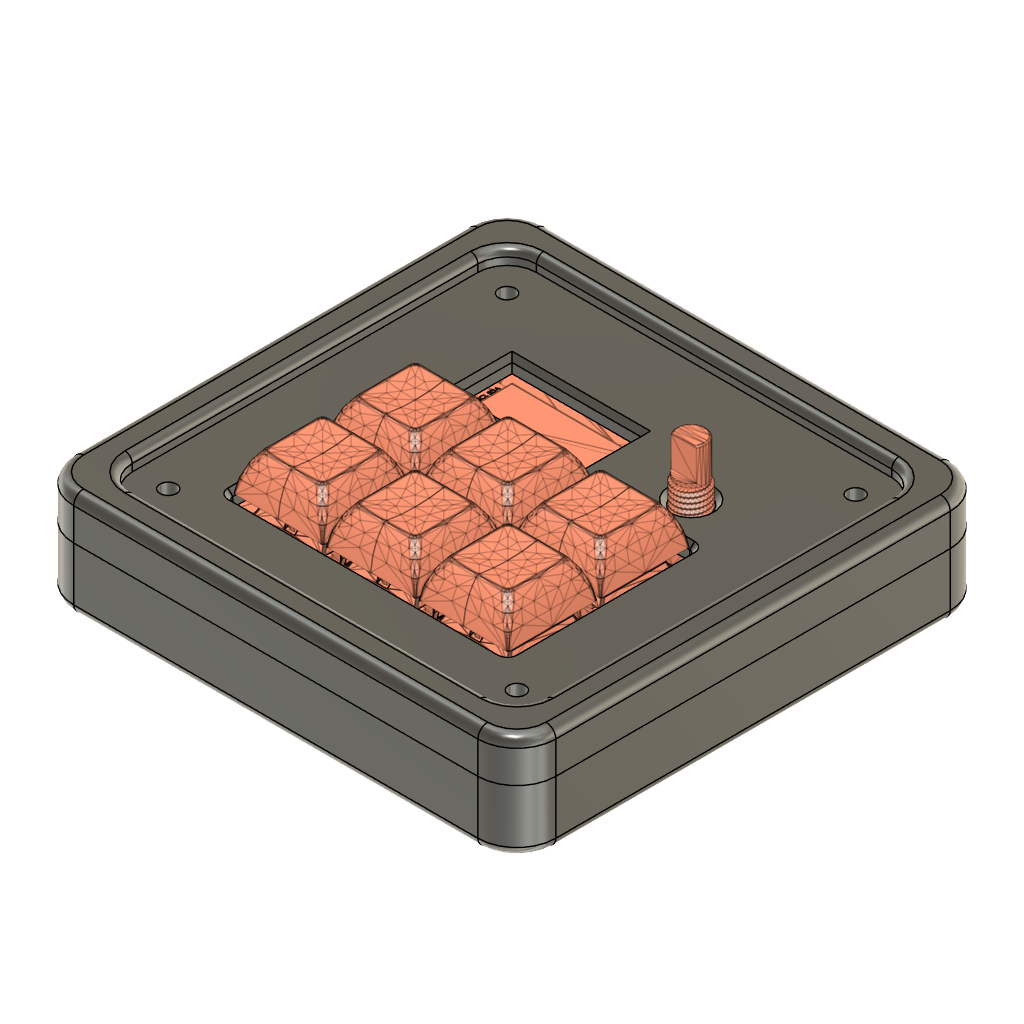
SpacePad-asssembled (Autodesk Fusion 360 archive; units mm, degrees)
design "SpacePad-Case.f3d"
part number: 2026-09-18-11-28-58-965
Autodesk Fusion 360 part; units mm, degrees
(part 1 of 3)
other "Base Mesh Feature4"
other "MeshRepair5"
sketch "Sketch97" plane through (0, 0, 0) normal (0, 0, 1) x (1, 0, 0)
  line L0 (39.25, 38.25) -> (-39.25, -38.25) construction
  line L1 (-39.25, 38.25) -> (39.25, -38.25) construction
  line L2 (-35.25, -38.45) -> (35.25, -38.45)
  arc A0 (35.25, -38.45) -> (39.45, -34.25) centre (35.25, -34.25) ccw
  line L3 (39.45, -34.25) -> (39.45, 34.25)
  arc A1 (39.45, 34.25) -> (35.25, 38.45) centre (35.25, 34.25) ccw
  line L4 (35.25, 38.45) -> (-35.25, 38.45)
  arc A2 (-35.25, 38.45) -> (-39.45, 34.25) centre (-35.25, 34.25) ccw
  line L5 (-39.45, 34.25) -> (-39.45, -34.25)
  arc A3 (-39.45, -34.25) -> (-35.25, -38.45) centre (-35.25, -34.25) ccw
  dimension "d507" = 78.5
  dimension "d508" = 76.5
  constraint coincident L0 origin
  constraint coincident L1 origin
  measures "d507" distance of L0.end L1.end
  measures "d508" distance of L1.start L0.end
extrude "Extrude107" add sketch "Sketch97" against normal blind 3 makes body 1
sketch "Sketch98" plane through (0, 0, -3) normal (0, 0, -1) x (1, 0, 0)
  arc A0 (-35.25, 38.45) -> (-39.45, 34.25) centre (-35.25, 34.25) ccw
  line L0 (-39.45, 34.25) -> (-39.45, -34.25)
  arc A1 (-39.45, -34.25) -> (-35.25, -38.45) centre (-35.25, -34.25) ccw
  line L1 (-35.25, -38.45) -> (35.25, -38.45)
  arc A2 (35.25, -38.45) -> (39.45, -34.25) centre (35.25, -34.25) ccw
  line L2 (39.45, -34.25) -> (39.45, 34.25)
  arc A3 (39.45, 34.25) -> (35.25, 38.45) centre (35.25, 34.25) ccw
  line L3 (35.25, 38.45) -> (-35.25, 38.45)
  line L4 (49.45, -40.45) -> (49.45, 40.45)
  line L5 (41.45, 48.45) -> (-41.45, 48.45)
  line L6 (-49.45, 40.45) -> (-49.45, -40.45)
  line L7 (-41.45, -48.45) -> (41.45, -48.45)
  arc A4 (-49.45, -40.45) -> (-41.45, -48.45) centre (-41.45, -40.45) ccw
  arc A5 (41.45, -48.45) -> (49.45, -40.45) centre (41.45, -40.45) ccw
  arc A6 (49.45, 40.45) -> (41.45, 48.45) centre (41.45, 40.45) ccw
  arc A7 (-41.45, 48.45) -> (-49.45, 40.45) centre (-41.45, 40.45) ccw
  dimension "d514" = 10
  dimension "d515" = 10
  dimension "d516" = 10
  dimension "d517" = 10
  dimension "d518" = 8
  constraint tangent L7 A4
  constraint tangent L6 A4
  constraint tangent L7 A5
  constraint tangent L4 A5
  constraint equal A4 A5
  constraint tangent L4 A6
  constraint tangent L5 A6
  constraint equal A4 A6
  constraint tangent L5 A7
  constraint tangent L6 A7
  constraint equal A4 A7
  measures "d514" distance of L2 L4
  measures "d515" distance of L3 L5
  measures "d516" distance of L0 L6
  measures "d517" distance of L1 L7
  measures "d518" radius of A4
extrude "Extrude108" add sketch "Sketch98" against normal blind 13 bodies 1
sketch "Sketch99" plane through (0, 0, 0) normal (0, 0, 1) x (-1, 0, 0)
  arc A0 (39.45, 34.25) -> (35.25, 38.45) centre (35.25, 34.25) ccw
  line L0 (35.25, 38.45) -> (-35.25, 38.45)
  arc A1 (-35.25, 38.45) -> (-39.45, 34.25) centre (-35.25, 34.25) ccw
  line L1 (-39.45, 34.25) -> (-39.45, -34.25)
  arc A2 (-39.45, -34.25) -> (-35.25, -38.45) centre (-35.25, -34.25) ccw
  line L2 (-35.25, -38.45) -> (35.25, -38.45)
  arc A3 (35.25, -38.45) -> (39.45, -34.25) centre (35.25, -34.25) ccw
  line L3 (39.45, -34.25) -> (39.45, 34.25)
  circle A4 centre (-35.7393, 34.7536) radius 2.35
  circle A5 centre (35.6945, 34.7057) radius 2.35
  circle A6 centre (-35.7505, -34.7482) radius 2.35
  circle A7 centre (35.7575, -34.7463) radius 2.35
  circle A8 centre (35.7575, -34.7463) radius 3.5
  circle A9 centre (-35.7505, -34.7482) radius 3.5
  circle A10 centre (-35.7393, 34.7536) radius 3.5
  circle A11 centre (35.6945, 34.7057) radius 3.5
  line L4 (35.6945, 31.2057) -> (39.45, 31.2057)
  line L5 (32.1945, 34.7057) -> (32.1945, 38.45)
  line L6 (32.2575, -34.7463) -> (32.2575, -38.45)
  line L7 (35.7575, -31.2463) -> (39.45, -31.2463)
  line L8 (-32.2505, -34.7482) -> (-32.2505, -38.45)
  line L9 (-35.7505, -31.2482) -> (-39.45, -31.2482)
  line L10 (-35.7393, 31.2536) -> (-39.45, 31.2536)
  line L11 (-32.2393, 34.7536) -> (-32.2393, 38.45)
  dimension "d521" = 4.7
  dimension "d522" = 4.7
  dimension "d523" = 4.7
  dimension "d524" = 4.7
  dimension "d525" = 7
  dimension "d526" = 7
  dimension "d527" = 7
  dimension "d528" = 7
  constraint concentric A7 A8
  constraint concentric A6 A9
  constraint concentric A4 A10
  constraint concentric A5 A11
  constraint coincident A11 L4.start
  constraint coincident L3 L4.end
  constraint tangent A11 L4
  constraint perpendicular L3 L4
  constraint coincident A11 L5.start
  constraint coincident L0 L5.end
  constraint tangent A11 L5
  constraint perpendicular L0 L5
  constraint coincident A8 L6.start
  constraint coincident L2 L6.end
  constraint tangent A8 L6
  constraint perpendicular L2 L6
  constraint coincident A8 L7.start
  constraint coincident L3 L7.end
  constraint tangent A8 L7
  constraint perpendicular L3 L7
  constraint coincident A9 L8.start
  constraint coincident L2 L8.end
  constraint tangent A9 L8
  constraint perpendicular L2 L8
  constraint coincident A9 L9.start
  constraint coincident L1 L9.end
  constraint tangent A9 L9
  constraint perpendicular L1 L9
  constraint coincident A10 L10.start
  constraint coincident L1 L10.end
  constraint tangent A10 L10
  constraint perpendicular L1 L10
  constraint coincident A10 L11.start
  constraint coincident L0 L11.end
  constraint tangent A10 L11
  constraint perpendicular L0 L11
  measures "d521" diameter of A4
  measures "d522" diameter of A5
  measures "d523" diameter of A6
  measures "d524" diameter of A7
  measures "d525" diameter of A8
  measures "d526" diameter of A9
  measures "d527" diameter of A10
  measures "d528" diameter of A11
extrude "Extrude109" add sketch "Sketch99" along normal blind 4 contours A0 L0 L3 A11 L4 L5 | A3 L3 A8 L7 | A11 | L0 A1 A10 L11 | A3 A8 | A1 A10 | L2 A3 A8 L6 | A1 L1 A10 L10 | A2 L2 A9 L8 | L1 A2 A9 L9 | A2 A9 picked at (38.4851, -36.238) picked at (-35.9802, -31.6463) bodies 1
other "Modify12"
other "Modify13"
sketch "Sketch100" plane through (0, 48.45, 0) normal (0, 1, 0) x (-1, 0, 0)
  line L0 (41.45, -3) -> (41.45, 10)
  line L1 (41.45, 10) -> (-41.45, 10)
  line L2 (-41.45, 10) -> (-41.45, -3)
  line L3 (-4.6681, 1.5118) -> (-4.6681, 1.1341)
  line L4 (-4.6681, 1.1341) -> (-4.6681, 0.8012)
  arc A0 (-4.6681, 0.8012) -> (-3.2181, -0.6488) centre (-3.2181, 0.8012) ccw
  line L5 (-3.2181, -0.6488) -> (3.2225, -0.6488)
  arc A1 (3.2225, -0.6488) -> (4.6725, 0.8012) centre (3.2225, 0.8012) ccw
  line L6 (4.6725, 0.8012) -> (4.6725, 1.1341)
  line L7 (4.6725, 1.1341) -> (4.6725, 1.5118)
  arc A2 (4.6725, 1.5118) -> (3.2225, 2.9618) centre (3.2225, 1.5118) ccw
  line L8 (3.2225, 2.9618) -> (-3.2181, 2.9618)
  arc A3 (-3.2181, 2.9618) -> (-4.6681, 1.5118) centre (-3.2181, 1.5118) ccw
  line L9 (-41.45, -3) -> (41.45, -3)
extrude "Extrude110" cut sketch "Sketch100" against normal blind 10 contours L3 L4 A0 L5 A1 L6 L7 A2 L8 A3 bodies 1
extrude "Extrude111" cut 1 faces at (-1.0756, 38.45, -0.2163) along direction (0, -1, 0) blind 1 on bodies 1 bodies 1
extrude "Extrude112" cut 1 faces at (-1.0756, 37.45, -0.2163) along direction (0, -1, 0) blind 0.001 on bodies 1 bodies 1
extrude "Extrude113" cut 1 faces at (-1.0756, 37.449, -0.2163) along direction (0, -1, 0) blind 8.5 on bodies 1 bodies 1
fillet "Fillet30" radius 2 8 edges at (-49.45, 0, -3) (-47.1069, 46.1069, -3) (0, 48.45, -3) (47.1069, 46.1069, -3) (49.45, 0, -3) (47.1069, -46.1069, -3) (0, -48.45, -3) (-47.1069, -46.1069, -3) on bodies 1
extrude "Extrude114" cut 1 faces at (-1.0756, 28.949, -0.2163) along direction (0, -1, 0) blind 3 on bodies 1 bodies 1
extrude "Extrude115" cut 1 faces at (-1.0756, 25.949, -0.2163) along direction (0, -1, 0) blind 0.5 on bodies 1 bodies 1
sketch "Sketch101" plane through (0, 0, 0) normal (0, 0, 1) x (1, 0, 0)
  line L0 (39.25, 38.25) -> (-39.25, -38.25) construction
  line L1 (-39.25, 38.25) -> (39.25, -38.25) construction
  line L2 (-35.45, -38.45) -> (35.45, -38.45)
  line L3 (39.45, -34.45) -> (39.45, 34.45)
  line L4 (35.45, 38.45) -> (-35.45, 38.45)
  line L5 (-39.45, 34.45) -> (-39.45, -34.45)
  arc A0 (-35.45, 38.45) -> (-39.45, 34.45) centre (-35.45, 34.45) ccw
  arc A1 (39.45, 34.45) -> (35.45, 38.45) centre (35.45, 34.45) ccw
  arc A2 (35.45, -38.45) -> (39.45, -34.45) centre (35.45, -34.45) ccw
  arc A3 (-39.45, -34.45) -> (-35.45, -38.45) centre (-35.45, -34.45) ccw
  line L6 (27.56, -29.5) -> (-27.77, -29.5)
  line L7 (-28.77, -28.5) -> (-28.77, 7.9)
  line L8 (-27.77, 8.9) -> (27.56, 8.9)
  line L9 (28.56, 7.9) -> (28.56, -28.5)
  arc A4 (27.56, -29.5) -> (28.56, -28.5) centre (27.56, -28.5) ccw
  arc A5 (-28.77, -28.5) -> (-27.77, -29.5) centre (-27.77, -28.5) ccw
  arc A6 (-27.77, 8.9) -> (-28.77, 7.9) centre (-27.77, 7.9) ccw
  arc A7 (28.56, 7.9) -> (27.56, 8.9) centre (27.56, 7.9) ccw
  line L10 (2.4481, 12.55) -> (-23.9519, 12.55)
  line L11 (-23.9519, 12.55) -> (-23.9519, 23.95)
  line L12 (-23.9519, 23.95) -> (2.4481, 23.95)
  line L13 (2.4481, 23.95) -> (2.4481, 12.55)
  circle A8 centre (19.7639, 16.9931) radius 3.6
  dimension "d549" = 78.5
  dimension "d550" = 76.5
  dimension "d552" = 4
  dimension "d556" = 1
  dimension "d558" = 7.2
  constraint coincident L0 origin
  constraint coincident L1 origin
  constraint tangent L4 A0
  constraint tangent L5 A0
  constraint tangent L4 A1
  constraint tangent L3 A1
  constraint equal A0 A1
  constraint tangent L3 A2
  constraint tangent L2 A2
  constraint equal A0 A2
  constraint tangent L2 A3
  constraint tangent L5 A3
  constraint equal A0 A3
  constraint tangent L9 A4
  constraint tangent L6 A4
  constraint tangent L6 A5
  constraint tangent L7 A5
  constraint equal A4 A5
  constraint tangent L7 A6
  constraint tangent L8 A6
  constraint equal A4 A6
  constraint tangent L8 A7
  constraint tangent L9 A7
  constraint equal A4 A7
  measures "d549" distance of L0.end L1.end
  measures "d550" distance of L1.start L0.end
  measures "d552" radius of A0
  measures "d556" radius of A4
  measures "d558" diameter of A8
extrude "Extrude116" add sketch "Sketch101" along normal blind 3 separate body makes body 2
chamfer "Chamfer18" distance 1 angle 45 8 edges at (-0.105, 8.9, 3) (28.2671, 8.6071, 3) (28.56, -10.3, 3) (28.2671, -29.2071, 3) (-0.105, -29.5, 3) (-28.4771, -29.2071, 3) (-28.77, -10.3, 3) (-28.4771, 8.6071, 3) tangent chain off on bodies 2
chamfer "Chamfer19" distance 1 angle 45 4 edges at (-10.7519, 23.95, 3) (2.4481, 18.25, 3) (-10.7519, 12.55, 3) (-23.9519, 18.25, 3) tangent chain off on bodies 2
chamfer "Chamfer20" distance 1 angle 45 1 edges at (16.4076, 18.2949, 3) tangent chain off on bodies 2
sketch "Sketch102" plane through (0, 0, 3) normal (0, 0, 1) x (-1, 0, 0)
  line L0 (-3.4481, -11.55) -> (24.9519, -11.55)
  line L1 (24.9519, -11.55) -> (24.9519, -24.95)
  line L2 (24.9519, -24.95) -> (-3.4481, -24.95)
  line L3 (-3.4481, -24.95) -> (-3.4481, -11.55)
  arc A0 (39.45, 34.45) -> (35.45, 38.45) centre (35.45, 34.45) ccw
  line L4 (35.45, 38.45) -> (-35.45, 38.45)
  arc A1 (-35.45, 38.45) -> (-39.45, 34.45) centre (-35.45, 34.45) ccw
  line L5 (-39.45, 34.45) -> (-39.45, -34.45)
  arc A2 (-39.45, -34.45) -> (-35.45, -38.45) centre (-35.45, -34.45) ccw
  line L6 (-35.45, -38.45) -> (35.45, -38.45)
  arc A3 (35.45, -38.45) -> (39.45, -34.45) centre (35.45, -34.45) ccw
  line L7 (39.45, -34.45) -> (39.45, 34.45)
  line L8 (27.77, -9.9) -> (-27.56, -9.9)
  arc A4 (-29.56, -7.9) -> (-27.56, -9.9) centre (-27.56, -7.9) ccw
  line L9 (-29.56, -7.9) -> (-29.56, 28.5)
  arc A5 (-27.56, 30.5) -> (-29.56, 28.5) centre (-27.56, 28.5) ccw
  line L10 (-27.56, 30.5) -> (27.77, 30.5)
  arc A6 (29.77, 28.5) -> (27.77, 30.5) centre (27.77, 28.5) ccw
  line L11 (29.77, 28.5) -> (29.77, -7.9)
  arc A7 (27.77, -9.9) -> (29.77, -7.9) centre (27.77, -7.9) ccw
  circle A8 centre (-19.7639, -16.9931) radius 4.6
  line L12 (41.45, 48.45) -> (-41.45, 48.45)
  line L13 (-49.45, 40.45) -> (-49.45, -40.45)
  line L14 (-41.45, -48.45) -> (41.45, -48.45)
  line L15 (49.45, -40.45) -> (49.45, 40.45)
  arc A9 (41.45, -48.45) -> (49.45, -40.45) centre (41.45, -40.45) ccw
  arc A10 (-49.45, -40.45) -> (-41.45, -48.45) centre (-41.45, -40.45) ccw
  arc A11 (-41.45, 48.45) -> (-49.45, 40.45) centre (-41.45, 40.45) ccw
  arc A12 (49.45, 40.45) -> (41.45, 48.45) centre (41.45, 40.45) ccw
  dimension "d565" = 10
  dimension "d566" = 10
  dimension "d567" = 10
  dimension "d568" = 10
  dimension "d569" = 8
  constraint tangent L14 A9
  constraint tangent L15 A9
  constraint tangent L14 A10
  constraint tangent L13 A10
  constraint equal A9 A10
  constraint tangent L13 A11
  constraint tangent L12 A11
  constraint equal A9 A11
  constraint tangent L12 A12
  constraint tangent L15 A12
  constraint equal A9 A12
  measures "d565" distance of L4 L12
  measures "d566" distance of L5 L13
  measures "d567" distance of L6 L14
  measures "d568" distance of L7 L15
  measures "d569" radius of A9
extrude "Extrude117" add sketch "Sketch102" against normal blind 10 contours L12 L13 L14 L15 A9 A10 A11 A12 bodies 2
move_body "Move9" bodies 2 to x (1, 0, 0) y (0, 1, 0) z (0, 0, 1) at (0, 0, 5)
move_body "Move10" bodies 2 to x (1, 0, 0) y (0, 1, 0) z (0, 0, 1) at (0, 0, 7.63)
extrude "Extrude118" cut 1 faces at (11.8167, -45.1167, 5.63) along direction (0, 0, 1) blind 4.37 on bodies 2 bodies 2
delete_face "DeleteFace30" 8 faces at (-45.4319, -47.3469, -1.3785) (13.8167, -46.5452, -2.9977) (-47.5452, -13.4833, -2.9977) (46.0695, -46.9372, -1.3785) (47.5452, 13.4833, -2.9977) (46.3729, 46.71, -1.3785) (-13.8167, 46.5452, -2.9977) (-48.3469, 44.4319, -1.3785) on bodies 1
fillet "Fillet31" radius 2 16 edges at (0, -48.45, -3) (-47.1069, -46.1069, -3) (-49.45, 0, -3) (-47.1069, 46.1069, -3) (0, 48.45, -3) (47.1069, 46.1069, -3) (49.45, 0, -3) (47.1069, -46.1069, -3) (0, 48.45, 15.63) (-47.1069, 46.1069, 15.63) (-49.45, 0, 15.63) (-47.1069, -46.1069, 15.63) (0, -48.45, 15.63) (47.1069, -46.1069, 15.63) (49.45, 0, 15.63) (47.1069, 46.1069, 15.63) on bodies 1 2
sketch "Sketch103" plane through (0, 0, 12.63) normal (0, 0, -1) x (1, 0, 0)
  arc A0 (28.56, 28.5) -> (27.56, 29.5) centre (27.56, 28.5) ccw
  line L0 (28.56, 28.5) -> (28.56, -7.9)
  arc A1 (27.56, -8.9) -> (28.56, -7.9) centre (27.56, -7.9) ccw
  line L1 (27.56, -8.9) -> (-27.77, -8.9)
  arc A2 (-28.77, -7.9) -> (-27.77, -8.9) centre (-27.77, -7.9) ccw
  line L2 (-28.77, -7.9) -> (-28.77, 28.5)
  arc A3 (-27.77, 29.5) -> (-28.77, 28.5) centre (-27.77, 28.5) ccw
  line L3 (-27.77, 29.5) -> (27.56, 29.5)
  circle A4 centre (19.7639, -16.9931) radius 3.6
  line L4 (2.4481, -23.95) -> (-23.9519, -23.95)
  line L5 (-23.9519, -23.95) -> (-23.9519, -12.55)
  line L6 (-23.9519, -12.55) -> (2.4481, -12.55)
  line L7 (2.4481, -12.55) -> (2.4481, -23.95)
  arc A5 (-35.45, 38.45) -> (-39.45, 34.45) centre (-35.45, 34.45) ccw
  line L8 (-39.45, 34.45) -> (-39.45, -34.45)
  arc A6 (-39.45, -34.45) -> (-35.45, -38.45) centre (-35.45, -34.45) ccw
  line L9 (-35.45, -38.45) -> (35.45, -38.45)
  arc A7 (35.45, -38.45) -> (39.45, -34.45) centre (35.45, -34.45) ccw
  line L10 (39.45, -34.45) -> (39.45, 34.45)
  arc A8 (39.45, 34.45) -> (35.45, 38.45) centre (35.45, 34.45) ccw
  line L11 (35.45, 38.45) -> (-35.45, 38.45)
  circle A9 centre (35.7497, 34.7499) radius 1.7
  circle A10 centre (-35.7575, 34.7473) radius 1.7
  circle A11 centre (35.7482, -34.7503) radius 1.7
  circle A12 centre (-35.7567, -34.7538) radius 1.7
  dimension "d576" = 3.4
  dimension "d577" = 3.4
  dimension "d578" = 3.4
  dimension "d579" = 3.4
  measures "d576" diameter of A9
  measures "d577" diameter of A10
  measures "d578" diameter of A11
  measures "d579" diameter of A12
extrude "Extrude119" cut sketch "Sketch103" against normal blind 3 contours A9 | A10 | A11 | A12 bodies 2
sketch "Sketch104" plane through (0, 0, -3) normal (0, 0, -1) x (1, 0, 0)
  line L0 (41.45, 46.45) -> (-41.45, 46.45)
  arc A0 (-41.45, 46.45) -> (-47.45, 40.45) centre (-41.45, 40.45) ccw
  line L1 (-47.45, 40.45) -> (-47.45, -40.45)
  arc A1 (-47.45, -40.45) -> (-41.45, -46.45) centre (-41.45, -40.45) ccw
  line L2 (-41.45, -46.45) -> (41.45, -46.45)
  arc A2 (41.45, -46.45) -> (47.45, -40.45) centre (41.45, -40.45) ccw
  line L3 (47.45, -40.45) -> (47.45, 40.45)
  arc A3 (47.45, 40.45) -> (41.45, 46.45) centre (41.45, 40.45) ccw
  spline S0 degree 3 poles (4.3219, 28.9081) (4.3299, 29.059) (4.306, 29.3606) (4.2822, 29.5035) knots 0 0 0 0 1 1 1 1
  spline S1 degree 3 poles (4.2822, 29.5035) (4.2584, 29.6463) (4.2267, 29.6622) (4.1632, 29.7416) knots 0 0 0 0 1 1 1 1
  spline S2 degree 3 poles (4.1632, 29.7416) (4.0997, 29.821) (4.06, 29.9083) (3.925, 29.9797) knots 0 0 0 0 1 1 1 1
  spline S3 degree 3 poles (3.925, 29.9797) (3.7901, 30.0511) (3.5361, 30.1543) (3.3694, 30.1781) knots 0 0 0 0 1 1 1 1
  spline S4 degree 3 poles (3.3694, 30.1781) (3.2027, 30.202) (3.0678, 30.1702) (2.9329, 30.1385) knots 0 0 0 0 1 1 1 1
  spline S5 degree 3 poles (2.9329, 30.1385) (2.7979, 30.1067) (2.7503, 30.1385) (2.5757, 29.9797) knots 0 0 0 0 1 1 1 1
  spline S6 degree 3 poles (2.5757, 29.9797) (2.401, 29.821) (2.2502, 29.7178) (1.8613, 29.186) knots 0 0 0 0 1 1 1 1
  spline S7 degree 3 poles (1.8613, 29.186) (1.4724, 28.6542) (0.5516, 27.2333) (0.2341, 26.8047) knots 0 0 0 0 1 1 1 1
  spline S8 degree 3 poles (0.2341, 26.8047) (-0.0834, 26.3761) (0.0754, 26.5666) (-0.0437, 26.6063) knots 0 0 0 0 1 1 1 1
  spline S9 degree 3 poles (-0.0437, 26.6063) (-0.1628, 26.646) (-0.139, 26.5745) (-0.4803, 27.0428) knots 0 0 0 0 1 1 1 1
  spline S10 degree 3 poles (-0.4803, 27.0428) (-0.8216, 27.5111) (-1.7344, 28.932) (-2.1075, 29.4241) knots 0 0 0 0 1 1 1 1
  spline S11 degree 3 poles (-2.1075, 29.4241) (-2.4805, 29.9162) (-2.5281, 29.8924) (-2.7028, 30.0194) knots 0 0 0 0 1 1 1 1
  spline S12 degree 3 poles (-2.7028, 30.0194) (-2.8774, 30.1464) (-2.9965, 30.1543) (-3.1393, 30.1781) knots 0 0 0 0 1 1 1 1
  spline S13 degree 3 poles (-3.1393, 30.1781) (-3.2822, 30.202) (-3.4568, 30.194) (-3.5759, 30.1781) knots 0 0 0 0 1 1 1 1
  spline S14 degree 3 poles (-3.5759, 30.1781) (-3.695, 30.1623) (-3.7346, 30.1702) (-3.8537, 30.0988) knots 0 0 0 0 1 1 1 1
  spline S15 degree 3 poles (-3.8537, 30.0988) (-3.9728, 30.0273) (-4.195, 29.8368) (-4.2903, 29.7416) knots 0 0 0 0 1 1 1 1
  spline S16 degree 3 poles (-4.2903, 29.7416) (-4.3855, 29.6463) (-4.3776, 29.6305) (-4.4093, 29.5431) knots 0 0 0 0 1 1 1 1
  spline S17 degree 3 poles (-4.4093, 29.5431) (-4.4411, 29.4558) (-4.4808, 29.3606) (-4.4887, 29.2256) knots 0 0 0 0 1 1 1 1
  spline S18 degree 3 poles (-4.4887, 29.2256) (-4.4966, 29.0907) (-4.4966, 28.8843) (-4.449, 28.7097) knots 0 0 0 0 1 1 1 1
  spline S19 degree 3 poles (-4.449, 28.7097) (-4.4014, 28.5351) (-4.4728, 28.5827) (-4.2109, 28.1541) knots 0 0 0 0 1 1 1 1
  spline S20 degree 3 poles (-4.2109, 28.1541) (-3.949, 27.7255) (-3.3616, 26.8206) (-2.8615, 26.13) knots 0 0 0 0 1 1 1 1
  spline S21 degree 3 poles (-2.8615, 26.13) (-2.3615, 25.4395) (-1.536, 24.4393) (-1.1946, 24.0266) knots 0 0 0 0 1 1 1 1
  spline S22 degree 3 poles (-1.1946, 24.0266) (-0.8533, 23.6138) (-0.9565, 23.7329) (-0.7978, 23.6297) knots 0 0 0 0 1 1 1 1
  spline S23 degree 3 poles (-0.7978, 23.6297) (-0.639, 23.5265) (-0.4009, 23.4313) (-0.2421, 23.3916) knots 0 0 0 0 1 1 1 1
  spline S24 degree 3 poles (-0.2421, 23.3916) (-0.0834, 23.3519) (0.0436, 23.3757) (0.1547, 23.3916) knots 0 0 0 0 1 1 1 1
  spline S25 degree 3 poles (0.1547, 23.3916) (0.2659, 23.4075) (0.3373, 23.4233) (0.4325, 23.471) knots 0 0 0 0 1 1 1 1
  spline S26 degree 3 poles (0.4325, 23.471) (0.5278, 23.5186) (0.6548, 23.598) (0.75, 23.6694) knots 0 0 0 0 1 1 1 1
  spline S27 degree 3 poles (0.75, 23.6694) (0.8453, 23.7408) (0.5437, 23.3281) (0.9882, 23.9075) knots 0 0 0 0 1 1 1 1
  spline S28 degree 3 poles (0.9882, 23.9075) (1.4327, 24.487) (2.9249, 26.4634) (3.4091, 27.1222) knots 0 0 0 0 1 1 1 1
  spline S29 degree 3 poles (3.4091, 27.1222) (3.8933, 27.781) (3.7504, 27.6302) (3.8854, 27.8763) knots 0 0 0 0 1 1 1 1
  spline S30 degree 3 poles (3.8854, 27.8763) (4.0203, 28.1223) (4.1711, 28.416) (4.2425, 28.5906) knots 0 0 0 0 1 1 1 1
  spline S31 degree 3 poles (4.2425, 28.5906) (4.314, 28.7653) (4.314, 28.7573) (4.3219, 28.9081) knots 0 0 0 0 1 1 1 1
  spline S32 degree 3 poles (3.6472, 29.0669) (3.6552, 28.9637) (3.6552, 28.9717) (3.5679, 28.7891) knots 0 0 0 0 1 1 1 1
  spline S33 degree 3 poles (3.5679, 28.7891) (3.4805, 28.6065) (3.3377, 28.289) (3.1313, 27.9556) knots 0 0 0 0 1 1 1 1
  spline S34 degree 3 poles (3.1313, 27.9556) (2.9249, 27.6223) (2.7979, 27.4238) (2.3375, 26.8047) knots 0 0 0 0 1 1 1 1
  spline S35 degree 3 poles (2.3375, 26.8047) (1.8772, 26.1856) (0.7659, 24.7251) (0.3929, 24.2647) knots 0 0 0 0 1 1 1 1
  spline S36 degree 3 poles (0.3929, 24.2647) (0.0198, 23.8043) (0.1706, 24.098) (0.0754, 24.0663) knots 0 0 0 0 1 1 1 1
  spline S37 degree 3 poles (0.0754, 24.0663) (-0.0199, 24.0345) (-0.0834, 24.0425) (-0.1628, 24.0663) knots 0 0 0 0 1 1 1 1
  spline S38 degree 3 poles (-0.1628, 24.0663) (-0.2421, 24.0901) (-0.2263, 24.0107) (-0.4009, 24.1853) knots 0 0 0 0 1 1 1 1
  spline S39 degree 3 poles (-0.4009, 24.1853) (-0.5755, 24.36) (-0.7422, 24.5187) (-1.1946, 25.0981) knots 0 0 0 0 1 1 1 1
  spline S40 degree 3 poles (-1.1946, 25.0981) (-1.6471, 25.6776) (-2.671, 27.0508) (-3.0996, 27.6778) knots 0 0 0 0 1 1 1 1
  spline S41 degree 3 poles (-3.0996, 27.6778) (-3.5283, 28.3049) (-3.6632, 28.6065) (-3.7743, 28.8685) knots 0 0 0 0 1 1 1 1
  spline S42 degree 3 poles (-3.7743, 28.8685) (-3.8855, 29.1304) (-3.7981, 29.1701) (-3.7743, 29.2653) knots 0 0 0 0 1 1 1 1
  spline S43 degree 3 poles (-3.7743, 29.2653) (-3.7505, 29.3606) (-3.7108, 29.4241) (-3.6156, 29.4638) knots 0 0 0 0 1 1 1 1
  spline S44 degree 3 poles (-3.6156, 29.4638) (-3.5203, 29.5035) (-3.3219, 29.5193) (-3.2187, 29.5035) knots 0 0 0 0 1 1 1 1
  spline S45 degree 3 poles (-3.2187, 29.5035) (-3.1155, 29.4876) (-3.1235, 29.5273) (-2.9806, 29.3844) knots 0 0 0 0 1 1 1 1
  spline S46 degree 3 poles (-2.9806, 29.3844) (-2.8377, 29.2415) (-2.7266, 29.1066) (-2.3853, 28.6303) knots 0 0 0 0 1 1 1 1
  spline S47 degree 3 poles (-2.3853, 28.6303) (-2.044, 28.1541) (-1.2661, 26.9476) (-0.9565, 26.5269) knots 0 0 0 0 1 1 1 1
  spline S48 degree 3 poles (-0.9565, 26.5269) (-0.647, 26.1062) (-0.6311, 26.1856) (-0.52, 26.0903) knots 0 0 0 0 1 1 1 1
  spline S49 degree 3 poles (-0.52, 26.0903) (-0.4088, 25.9951) (-0.3691, 25.9951) (-0.2818, 25.9713) knots 0 0 0 0 1 1 1 1
  spline S50 degree 3 poles (-0.2818, 25.9713) (-0.1945, 25.9475) (-0.131, 25.9157) (-0.004, 25.9316) knots 0 0 0 0 1 1 1 1
  spline S51 degree 3 poles (-0.004, 25.9316) (0.123, 25.9475) (0.3373, 26.003) (0.4722, 26.0903) knots 0 0 0 0 1 1 1 1
  spline S52 degree 3 poles (0.4722, 26.0903) (0.6072, 26.1776) (0.496, 25.9951) (0.8294, 26.4475) knots 0 0 0 0 1 1 1 1
  spline S53 degree 3 poles (0.8294, 26.4475) (1.1628, 26.9) (2.0994, 28.3287) (2.4566, 28.8288) knots 0 0 0 0 1 1 1 1
  spline S54 degree 3 poles (2.4566, 28.8288) (2.8138, 29.3288) (2.8535, 29.313) (2.9725, 29.4241) knots 0 0 0 0 1 1 1 1
  spline S55 degree 3 poles (2.9725, 29.4241) (3.0916, 29.5352) (3.0757, 29.5035) (3.171, 29.5035) knots 0 0 0 0 1 1 1 1
  spline S56 degree 3 poles (3.171, 29.5035) (3.2662, 29.5035) (3.4488, 29.4955) (3.5282, 29.4241) knots 0 0 0 0 1 1 1 1
  spline S57 degree 3 poles (3.5282, 29.4241) (3.6075, 29.3526) (3.6393, 29.1701) (3.6472, 29.0669) knots 0 0 0 0 1 1 1 1
  spline S58 degree 3 poles (-14.8471, -14.9069) (-14.4582, -14.883) (-14.101, -14.8513) (-13.6962, -14.7481) knots 0 0 0 0 1 1 1 1
  spline S59 degree 3 poles (-13.6962, -14.7481) (-13.2914, -14.6449) (-12.8072, -14.4782) (-12.4262, -14.3115) knots 0 0 0 0 1 1 1 1
  spline S60 degree 3 poles (-12.4262, -14.3115) (-12.0452, -14.1449) (-11.7674, -13.994) (-11.3943, -13.7559) knots 0 0 0 0 1 1 1 1
  spline S61 degree 3 poles (-11.3943, -13.7559) (-11.0213, -13.5178) (-10.6006, -13.2162) (-10.2037, -12.8828) knots 0 0 0 0 1 1 1 1
  spline S62 degree 3 poles (-10.2037, -12.8828) (-9.8068, -12.5494) (-9.2909, -12.0176) (-9.0131, -11.7319) knots 0 0 0 0 1 1 1 1
  spline S63 degree 3 poles (-9.0131, -11.7319) (-8.7353, -11.4461) (-8.775, -11.4937) (-8.5368, -11.1762) knots 0 0 0 0 1 1 1 1
  spline S64 degree 3 poles (-8.5368, -11.1762) (-8.2987, -10.8587) (-7.886, -10.3031) (-7.5843, -9.8269) knots 0 0 0 0 1 1 1 1
  spline S65 degree 3 poles (-7.5843, -9.8269) (-7.2827, -9.3506) (-7.0366, -8.8982) (-6.7509, -8.3187) knots 0 0 0 0 1 1 1 1
  spline S66 degree 3 poles (-6.7509, -8.3187) (-6.4651, -7.7393) (-6.1238, -6.9455) (-5.8778, -6.3344) knots 0 0 0 0 1 1 1 1
  spline S67 degree 3 poles (-5.8778, -6.3344) (-5.6317, -5.7232) (-5.4571, -5.1914) (-5.2825, -4.6278) knots 0 0 0 0 1 1 1 1
  spline S68 degree 3 poles (-5.2825, -4.6278) (-5.1078, -4.0642) (-4.9808, -3.6753) (-4.8062, -2.9609) knots 0 0 0 0 1 1 1 1
  spline S69 degree 3 poles (-4.8062, -2.9609) (-4.6316, -2.2465) (-4.3935, -1.1353) (-4.2506, -0.3415) knots 0 0 0 0 1 1 1 1
  spline S70 degree 3 poles (-4.2506, -0.3415) (-4.1077, 0.4522) (-4.0283, 0.9602) (-3.9331, 1.8016) knots 0 0 0 0 1 1 1 1
  spline S71 degree 3 poles (-3.9331, 1.8016) (-3.8378, 2.643) (-3.7346, 3.7463) (-3.695, 4.6988) knots 0 0 0 0 1 1 1 1
  spline S72 degree 3 poles (-3.695, 4.6988) (-3.6553, 5.6513) (-3.6394, 6.4847) (-3.695, 7.5166) knots 0 0 0 0 1 1 1 1
  spline S73 degree 3 poles (-3.695, 7.5166) (-3.7505, 8.5485) (-3.9013, 9.9851) (-4.0125, 10.89) knots 0 0 0 0 1 1 1 1
  spline S74 degree 3 poles (-4.0125, 10.89) (-4.1236, 11.7949) (-4.2268, 12.2632) (-4.3696, 12.9538) knots 0 0 0 0 1 1 1 1
  spline S75 degree 3 poles (-4.3696, 12.9538) (-4.5125, 13.6443) (-4.7268, 14.4619) (-4.8856, 15.0175) knots 0 0 0 0 1 1 1 1
  spline S76 degree 3 poles (-4.8856, 15.0175) (-5.0443, 15.5731) (-5.1555, 15.8589) (-5.3221, 16.2875) knots 0 0 0 0 1 1 1 1
  spline S77 degree 3 poles (-5.3221, 16.2875) (-5.4888, 16.7161) (-5.6873, 17.1924) (-5.8778, 17.5972) knots 0 0 0 0 1 1 1 1
  spline S78 degree 3 poles (-5.8778, 17.5972) (-6.0683, 18.002) (-6.2508, 18.3275) (-6.4731, 18.7085) knots 0 0 0 0 1 1 1 1
  spline S79 degree 3 poles (-6.4731, 18.7085) (-6.6953, 19.0895) (-6.9573, 19.4863) (-7.2271, 19.8594) knots 0 0 0 0 1 1 1 1
  spline S80 degree 3 poles (-7.2271, 19.8594) (-7.497, 20.2325) (-7.8066, 20.6055) (-8.1003, 20.931) knots 0 0 0 0 1 1 1 1
  spline S81 degree 3 poles (-8.1003, 20.931) (-8.394, 21.2564) (-8.6321, 21.5104) (-8.9734, 21.8041) knots 0 0 0 0 1 1 1 1
  spline S82 degree 3 poles (-8.9734, 21.8041) (-9.3147, 22.0978) (-9.7116, 22.4153) (-10.1243, 22.6772) knots 0 0 0 0 1 1 1 1
  spline S83 degree 3 poles (-10.1243, 22.6772) (-10.5371, 22.9391) (-11.0451, 23.209) (-11.434, 23.3916) knots 0 0 0 0 1 1 1 1
  spline S84 degree 3 poles (-11.434, 23.3916) (-11.823, 23.5741) (-12.1087, 23.6773) (-12.4659, 23.7885) knots 0 0 0 0 1 1 1 1
  spline S85 degree 3 poles (-12.4659, 23.7885) (-12.8231, 23.8996) (-13.2358, 24.0028) (-13.5771, 24.0663) knots 0 0 0 0 1 1 1 1
  spline S86 degree 3 poles (-13.5771, 24.0663) (-13.9185, 24.1298) (-14.109, 24.1695) (-14.5296, 24.1853) knots 0 0 0 0 1 1 1 1
  spline S87 degree 3 poles (-14.5296, 24.1853) (-14.9503, 24.2012) (-15.6091, 24.2091) (-16.0775, 24.1853) knots 0 0 0 0 1 1 1 1
  spline S88 degree 3 poles (-16.0775, 24.1853) (-16.5458, 24.1615) (-16.9426, 24.098) (-17.3475, 24.0266) knots 0 0 0 0 1 1 1 1
  spline S89 degree 3 poles (-17.3475, 24.0266) (-17.7523, 23.9551) (-18.1095, 23.8678) (-18.4984, 23.7488) knots 0 0 0 0 1 1 1 1
  spline S90 degree 3 poles (-18.4984, 23.7488) (-18.8873, 23.6297) (-19.316, 23.471) (-19.689, 23.3122) knots 0 0 0 0 1 1 1 1
  spline S91 degree 3 poles (-19.689, 23.3122) (-20.0621, 23.1535) (-20.3478, 23.0106) (-20.7209, 22.7963) knots 0 0 0 0 1 1 1 1
  spline S92 degree 3 poles (-20.7209, 22.7963) (-21.094, 22.582) (-21.602, 22.2565) (-21.9512, 22.0025) knots 0 0 0 0 1 1 1 1
  spline S93 degree 3 poles (-21.9512, 22.0025) (-22.3005, 21.7485) (-22.5306, 21.5501) (-22.8243, 21.2881) knots 0 0 0 0 1 1 1 1
  spline S94 degree 3 poles (-22.8243, 21.2881) (-23.118, 21.0262) (-23.4038, 20.7405) (-23.6975, 20.415) knots 0 0 0 0 1 1 1 1
  spline S95 degree 3 poles (-23.6975, 20.415) (-23.9911, 20.0896) (-24.3166, 19.6927) (-24.5706, 19.3435) knots 0 0 0 0 1 1 1 1
  spline S96 degree 3 poles (-24.5706, 19.3435) (-24.8246, 18.9942) (-25.031, 18.6688) (-25.2453, 18.3116) knots 0 0 0 0 1 1 1 1
  spline S97 degree 3 poles (-25.2453, 18.3116) (-25.4596, 17.9544) (-25.658, 17.5893) (-25.8406, 17.2003) knots 0 0 0 0 1 1 1 1
  spline S98 degree 3 poles (-25.8406, 17.2003) (-26.0231, 16.8114) (-26.174, 16.4701) (-26.3565, 15.97) knots 0 0 0 0 1 1 1 1
  spline S99 degree 3 poles (-26.3565, 15.97) (-26.5391, 15.47) (-26.7772, 14.6683) (-26.9121, 14.1841) knots 0 0 0 0 1 1 1 1
  spline S100 degree 3 poles (-26.9121, 14.1841) (-27.0471, 13.6999) (-27.0709, 13.5332) (-27.1503, 13.0728) knots 0 0 0 0 1 1 1 1
  spline S101 degree 3 poles (-27.1503, 13.0728) (-27.2296, 12.6125) (-27.3328, 11.9536) (-27.3884, 11.4456) knots 0 0 0 0 1 1 1 1
  spline S102 degree 3 poles (-27.3884, 11.4456) (-27.444, 10.9376) (-27.4836, 10.6122) (-27.5075, 10.0169) knots 0 0 0 0 1 1 1 1
  spline S103 degree 3 poles (-27.5075, 10.0169) (-27.5313, 9.4216) (-27.5551, 8.5088) (-27.5471, 7.8738) knots 0 0 0 0 1 1 1 1
  spline S104 degree 3 poles (-27.5471, 7.8738) (-27.5392, 7.2388) (-27.5313, 6.9371) (-27.4678, 6.2069) knots 0 0 0 0 1 1 1 1
  spline S105 degree 3 poles (-27.4678, 6.2069) (-27.4043, 5.4766) (-27.2614, 4.2781) (-27.1503, 3.5081) knots 0 0 0 0 1 1 1 1
  spline S106 degree 3 poles (-27.1503, 3.5081) (-27.0391, 2.7382) (-26.9439, 2.3016) (-26.7931, 1.6031) knots 0 0 0 0 1 1 1 1
  spline S107 degree 3 poles (-26.7931, 1.6031) (-26.6423, 0.9046) (-26.42, 0.0236) (-26.2375, -0.6987) knots 0 0 0 0 1 1 1 1
  spline S108 degree 3 poles (-26.2375, -0.6987) (-26.0549, -1.421) (-25.9358, -1.8973) (-25.6818, -2.7228) knots 0 0 0 0 1 1 1 1
  spline S109 degree 3 poles (-25.6818, -2.7228) (-25.4278, -3.5483) (-25.023, -4.8342) (-24.7293, -5.6597) knots 0 0 0 0 1 1 1 1
  spline S110 degree 3 poles (-24.7293, -5.6597) (-24.4356, -6.4852) (-24.2213, -7.0329) (-23.9356, -7.6837) knots 0 0 0 0 1 1 1 1
  spline S111 degree 3 poles (-23.9356, -7.6837) (-23.6498, -8.3346) (-23.3006, -9.041) (-23.0228, -9.549) knots 0 0 0 0 1 1 1 1
  spline S112 degree 3 poles (-23.0228, -9.549) (-22.745, -10.057) (-22.5227, -10.3745) (-22.2687, -10.7397) knots 0 0 0 0 1 1 1 1
  spline S113 degree 3 poles (-22.2687, -10.7397) (-22.0147, -11.1048) (-21.7766, -11.4223) (-21.5146, -11.7319) knots 0 0 0 0 1 1 1 1
  spline S114 degree 3 poles (-21.5146, -11.7319) (-21.2527, -12.0414) (-21.0146, -12.3113) (-20.6812, -12.605) knots 0 0 0 0 1 1 1 1
  spline S115 degree 3 poles (-20.6812, -12.605) (-20.3478, -12.8987) (-19.9351, -13.2479) (-19.5303, -13.5178) knots 0 0 0 0 1 1 1 1
  spline S116 degree 3 poles (-19.5303, -13.5178) (-19.1255, -13.7877) (-18.6413, -14.0496) (-18.2603, -14.2322) knots 0 0 0 0 1 1 1 1
  spline S117 degree 3 poles (-18.2603, -14.2322) (-17.8793, -14.4147) (-17.6015, -14.5259) (-17.2284, -14.629) knots 0 0 0 0 1 1 1 1
  spline S118 degree 3 poles (-17.2284, -14.629) (-16.8553, -14.7322) (-16.4346, -14.8195) (-16.0378, -14.8672) knots 0 0 0 0 1 1 1 1
  spline S119 degree 3 poles (-16.0378, -14.8672) (-15.6409, -14.9148) (-15.2361, -14.9307) (-14.8471, -14.9069) knots 0 0 0 0 1 1 1 1
  spline S120 degree 3 poles (-14.8471, -14.2322) (-15.1885, -14.2639) (-15.3234, -14.2719) (-15.6806, -14.2322) knots 0 0 0 0 1 1 1 1
  spline S121 degree 3 poles (-15.6806, -14.2322) (-16.0378, -14.1925) (-16.6013, -14.0972) (-16.9903, -13.994) knots 0 0 0 0 1 1 1 1
  spline S122 degree 3 poles (-16.9903, -13.994) (-17.3792, -13.8909) (-17.665, -13.7718) (-18.0221, -13.5972) knots 0 0 0 0 1 1 1 1
  spline S123 degree 3 poles (-18.0221, -13.5972) (-18.3793, -13.4225) (-18.7603, -13.2162) (-19.1334, -12.9622) knots 0 0 0 0 1 1 1 1
  spline S124 degree 3 poles (-19.1334, -12.9622) (-19.5065, -12.7082) (-19.9827, -12.3113) (-20.2843, -12.0494) knots 0 0 0 0 1 1 1 1
  spline S125 degree 3 poles (-20.2843, -12.0494) (-20.586, -11.7874) (-20.6891, -11.6525) (-20.9193, -11.3747) knots 0 0 0 0 1 1 1 1
  spline S126 degree 3 poles (-20.9193, -11.3747) (-21.1495, -11.0969) (-21.3876, -10.8032) (-21.6734, -10.3825) knots 0 0 0 0 1 1 1 1
  spline S127 degree 3 poles (-21.6734, -10.3825) (-21.9591, -9.9618) (-22.3163, -9.422) (-22.6259, -8.8347) knots 0 0 0 0 1 1 1 1
  spline S128 degree 3 poles (-22.6259, -8.8347) (-22.9355, -8.2473) (-23.2926, -7.4218) (-23.5387, -6.8503) knots 0 0 0 0 1 1 1 1
  spline S129 degree 3 poles (-23.5387, -6.8503) (-23.7848, -6.2788) (-23.8483, -6.0962) (-24.0943, -5.3819) knots 0 0 0 0 1 1 1 1
  spline S130 degree 3 poles (-24.0943, -5.3819) (-24.3404, -4.6675) (-24.7611, -3.3737) (-25.0071, -2.564) knots 0 0 0 0 1 1 1 1
  spline S131 degree 3 poles (-25.0071, -2.564) (-25.2532, -1.7544) (-25.3802, -1.2623) (-25.5628, -0.54) knots 0 0 0 0 1 1 1 1
  spline S132 degree 3 poles (-25.5628, -0.54) (-25.7453, 0.1823) (-25.9676, 1.0634) (-26.1184, 1.7619) knots 0 0 0 0 1 1 1 1
  spline S133 degree 3 poles (-26.1184, 1.7619) (-26.2692, 2.4604) (-26.3724, 2.9763) (-26.4756, 3.6669) knots 0 0 0 0 1 1 1 1
  spline S134 degree 3 poles (-26.4756, 3.6669) (-26.5788, 4.3575) (-26.6899, 5.1988) (-26.7534, 5.9291) knots 0 0 0 0 1 1 1 1
  spline S135 degree 3 poles (-26.7534, 5.9291) (-26.8169, 6.6593) (-26.8566, 7.3737) (-26.8725, 8.0325) knots 0 0 0 0 1 1 1 1
  spline S136 degree 3 poles (-26.8725, 8.0325) (-26.8883, 8.6913) (-26.8566, 9.3184) (-26.8328, 9.8581) knots 0 0 0 0 1 1 1 1
  spline S137 degree 3 poles (-26.8328, 9.8581) (-26.809, 10.3979) (-26.7772, 10.7789) (-26.7137, 11.2869) knots 0 0 0 0 1 1 1 1
  spline S138 degree 3 poles (-26.7137, 11.2869) (-26.6502, 11.7949) (-26.555, 12.4537) (-26.4756, 12.9141) knots 0 0 0 0 1 1 1 1
  spline S139 degree 3 poles (-26.4756, 12.9141) (-26.3962, 13.3745) (-26.3645, 13.565) (-26.2375, 14.0253) knots 0 0 0 0 1 1 1 1
  spline S140 degree 3 poles (-26.2375, 14.0253) (-26.1105, 14.4857) (-25.8961, 15.208) (-25.7215, 15.6922) knots 0 0 0 0 1 1 1 1
  spline S141 degree 3 poles (-25.7215, 15.6922) (-25.5469, 16.1764) (-25.3802, 16.5495) (-25.2056, 16.9225) knots 0 0 0 0 1 1 1 1
  spline S142 degree 3 poles (-25.2056, 16.9225) (-25.031, 17.2956) (-24.8563, 17.6131) (-24.65, 17.9544) knots 0 0 0 0 1 1 1 1
  spline S143 degree 3 poles (-24.65, 17.9544) (-24.4436, 18.2957) (-24.2372, 18.637) (-23.9753, 18.9863) knots 0 0 0 0 1 1 1 1
  spline S144 degree 3 poles (-23.9753, 18.9863) (-23.7133, 19.3355) (-23.3641, 19.7641) (-23.1021, 20.0578) knots 0 0 0 0 1 1 1 1
  spline S145 degree 3 poles (-23.1021, 20.0578) (-22.8402, 20.3515) (-22.6815, 20.5023) (-22.4275, 20.7325) knots 0 0 0 0 1 1 1 1
  spline S146 degree 3 poles (-22.4275, 20.7325) (-22.1735, 20.9627) (-21.856, 21.2246) (-21.5543, 21.4469) knots 0 0 0 0 1 1 1 1
  spline S147 degree 3 poles (-21.5543, 21.4469) (-21.2527, 21.6691) (-20.9035, 21.8993) (-20.6018, 22.0819) knots 0 0 0 0 1 1 1 1
  spline S148 degree 3 poles (-20.6018, 22.0819) (-20.3002, 22.2645) (-20.1176, 22.3835) (-19.7287, 22.5581) knots 0 0 0 0 1 1 1 1
  spline S149 degree 3 poles (-19.7287, 22.5581) (-19.3398, 22.7328) (-18.6968, 22.9788) (-18.2603, 23.1138) knots 0 0 0 0 1 1 1 1
  spline S150 degree 3 poles (-18.2603, 23.1138) (-17.8237, 23.2487) (-17.4745, 23.3281) (-17.1093, 23.3916) knots 0 0 0 0 1 1 1 1
  spline S151 degree 3 poles (-17.1093, 23.3916) (-16.7442, 23.4551) (-16.5061, 23.4868) (-16.0775, 23.5106) knots 0 0 0 0 1 1 1 1
  spline S152 degree 3 poles (-16.0775, 23.5106) (-15.6488, 23.5345) (-14.9027, 23.5265) (-14.5296, 23.5106) knots 0 0 0 0 1 1 1 1
  spline S153 degree 3 poles (-14.5296, 23.5106) (-14.1566, 23.4948) (-14.1169, 23.4868) (-13.8153, 23.4313) knots 0 0 0 0 1 1 1 1
  spline S154 degree 3 poles (-13.8153, 23.4313) (-13.5136, 23.3757) (-13.0612, 23.2646) (-12.704, 23.1535) knots 0 0 0 0 1 1 1 1
  spline S155 degree 3 poles (-12.704, 23.1535) (-12.3468, 23.0423) (-12.0373, 22.9312) (-11.6721, 22.7566) knots 0 0 0 0 1 1 1 1
  spline S156 degree 3 poles (-11.6721, 22.7566) (-11.307, 22.582) (-10.9022, 22.3756) (-10.5212, 22.1216) knots 0 0 0 0 1 1 1 1
  spline S157 degree 3 poles (-10.5212, 22.1216) (-10.1402, 21.8676) (-9.6719, 21.5025) (-9.3703, 21.2485) knots 0 0 0 0 1 1 1 1
  spline S158 degree 3 poles (-9.3703, 21.2485) (-9.0686, 20.9945) (-8.9496, 20.8675) (-8.6956, 20.5738) knots 0 0 0 0 1 1 1 1
  spline S159 degree 3 poles (-8.6956, 20.5738) (-8.4416, 20.2801) (-8.0526, 19.8038) (-7.8225, 19.5022) knots 0 0 0 0 1 1 1 1
  spline S160 degree 3 poles (-7.8225, 19.5022) (-7.5923, 19.2006) (-7.5208, 19.1133) (-7.3065, 18.7481) knots 0 0 0 0 1 1 1 1
  spline S161 degree 3 poles (-7.3065, 18.7481) (-7.0922, 18.383) (-6.735, 17.7718) (-6.5128, 17.3194) knots 0 0 0 0 1 1 1 1
  spline S162 degree 3 poles (-6.5128, 17.3194) (-6.2905, 16.867) (-6.1397, 16.5098) (-5.9571, 16.0097) knots 0 0 0 0 1 1 1 1
  spline S163 degree 3 poles (-5.9571, 16.0097) (-5.7746, 15.5096) (-5.5523, 14.835) (-5.4015, 14.3031) knots 0 0 0 0 1 1 1 1
  spline S164 degree 3 poles (-5.4015, 14.3031) (-5.2507, 13.7713) (-5.1634, 13.3903) (-5.0443, 12.795) knots 0 0 0 0 1 1 1 1
  spline S165 degree 3 poles (-5.0443, 12.795) (-4.9253, 12.1997) (-4.7983, 11.6361) (-4.6871, 10.7313) knots 0 0 0 0 1 1 1 1
  spline S166 degree 3 poles (-4.6871, 10.7313) (-4.576, 9.8264) (-4.4252, 8.3341) (-4.3696, 7.3578) knots 0 0 0 0 1 1 1 1
  spline S167 degree 3 poles (-4.3696, 7.3578) (-4.3141, 6.3815) (-4.3458, 5.6275) (-4.3696, 4.8575) knots 0 0 0 0 1 1 1 1
  spline S168 degree 3 poles (-4.3696, 4.8575) (-4.3935, 4.0876) (-4.4649, 3.3891) (-4.5284, 2.7144) knots 0 0 0 0 1 1 1 1
  spline S169 degree 3 poles (-4.5284, 2.7144) (-4.5919, 2.0397) (-4.6633, 1.5) (-4.7665, 0.8094) knots 0 0 0 0 1 1 1 1
  spline S170 degree 3 poles (-4.7665, 0.8094) (-4.8697, 0.1188) (-5.0443, -0.8099) (-5.1634, -1.4131) knots 0 0 0 0 1 1 1 1
  spline S171 degree 3 poles (-5.1634, -1.4131) (-5.2825, -2.0164) (-5.3142, -2.191) (-5.4809, -2.8022) knots 0 0 0 0 1 1 1 1
  spline S172 degree 3 poles (-5.4809, -2.8022) (-5.6476, -3.4134) (-5.9413, -4.4214) (-6.1556, -5.0644) knots 0 0 0 0 1 1 1 1
  spline S173 degree 3 poles (-6.1556, -5.0644) (-6.3699, -5.7073) (-6.5445, -6.1518) (-6.7509, -6.6519) knots 0 0 0 0 1 1 1 1
  spline S174 degree 3 poles (-6.7509, -6.6519) (-6.9573, -7.1519) (-7.2033, -7.6599) (-7.3859, -8.0409) knots 0 0 0 0 1 1 1 1
  spline S175 degree 3 poles (-7.3859, -8.0409) (-7.5685, -8.4219) (-7.6478, -8.5965) (-7.8621, -8.9537) knots 0 0 0 0 1 1 1 1
  spline S176 degree 3 poles (-7.8621, -8.9537) (-8.0765, -9.3109) (-8.3622, -9.7792) (-8.6559, -10.184) knots 0 0 0 0 1 1 1 1
  spline S177 degree 3 poles (-8.6559, -10.184) (-8.9496, -10.5889) (-9.283, -11.0175) (-9.6084, -11.3747) knots 0 0 0 0 1 1 1 1
  spline S178 degree 3 poles (-9.6084, -11.3747) (-9.9338, -11.7319) (-10.2355, -12.0255) (-10.6006, -12.3272) knots 0 0 0 0 1 1 1 1
  spline S179 degree 3 poles (-10.6006, -12.3272) (-10.9657, -12.6288) (-11.4499, -12.978) (-11.7912, -13.2003) knots 0 0 0 0 1 1 1 1
  spline S180 degree 3 poles (-11.7912, -13.2003) (-12.1325, -13.4225) (-12.3627, -13.5337) (-12.6643, -13.6765) knots 0 0 0 0 1 1 1 1
  spline S181 degree 3 poles (-12.6643, -13.6765) (-12.966, -13.8194) (-13.2517, -13.9385) (-13.6168, -14.0337) knots 0 0 0 0 1 1 1 1
  spline S182 degree 3 poles (-13.6168, -14.0337) (-13.982, -14.129) (-14.5058, -14.2004) (-14.8471, -14.2322) knots 0 0 0 0 1 1 1 1
  spline S183 degree 3 poles (13.0135, -14.9069) (13.3548, -14.9069) (13.9025, -14.883) (14.2835, -14.8275) knots 0 0 0 0 1 1 1 1
  spline S184 degree 3 poles (14.2835, -14.8275) (14.6645, -14.7719) (14.9582, -14.6925) (15.3154, -14.5894) knots 0 0 0 0 1 1 1 1
  spline S185 degree 3 poles (15.3154, -14.5894) (15.6725, -14.4862) (15.99, -14.3909) (16.4266, -14.1925) knots 0 0 0 0 1 1 1 1
  spline S186 degree 3 poles (16.4266, -14.1925) (16.8632, -13.994) (17.4347, -13.7242) (17.9347, -13.3987) knots 0 0 0 0 1 1 1 1
  spline S187 degree 3 poles (17.9347, -13.3987) (18.4348, -13.0733) (18.9904, -12.6367) (19.4429, -12.2478) knots 0 0 0 0 1 1 1 1
  spline S188 degree 3 poles (19.4429, -12.2478) (19.8953, -11.8589) (20.2684, -11.4699) (20.6335, -11.0572) knots 0 0 0 0 1 1 1 1
  spline S189 degree 3 poles (20.6335, -11.0572) (20.9986, -10.6444) (21.2764, -10.3031) (21.6257, -9.7872) knots 0 0 0 0 1 1 1 1
  spline S190 degree 3 poles (21.6257, -9.7872) (21.9749, -9.2712) (22.4274, -8.5251) (22.7369, -7.9615) knots 0 0 0 0 1 1 1 1
  spline S191 degree 3 poles (22.7369, -7.9615) (23.0465, -7.398) (23.229, -7.0329) (23.491, -6.4137) knots 0 0 0 0 1 1 1 1
  spline S192 degree 3 poles (23.491, -6.4137) (23.7529, -5.7946) (24.0387, -5.0723) (24.3244, -4.2309) knots 0 0 0 0 1 1 1 1
  spline S193 degree 3 poles (24.3244, -4.2309) (24.6102, -3.3895) (24.9277, -2.3815) (25.1975, -1.3734) knots 0 0 0 0 1 1 1 1
  spline S194 degree 3 poles (25.1975, -1.3734) (25.4674, -0.3654) (25.7929, 1.0951) (25.9516, 1.8016) knots 0 0 0 0 1 1 1 1
  spline S195 degree 3 poles (25.9516, 1.8016) (26.1104, 2.508) (26.0786, 2.3969) (26.15, 2.8731) knots 0 0 0 0 1 1 1 1
  spline S196 degree 3 poles (26.15, 2.8731) (26.2215, 3.3494) (26.3326, 4.3257) (26.3882, 4.6591) knots 0 0 0 0 1 1 1 1
  spline S197 degree 3 poles (26.3882, 4.6591) (26.4437, 4.9925) (26.404, 4.3098) (26.4675, 4.8972) knots 0 0 0 0 1 1 1 1
  spline S198 degree 3 poles (26.4675, 4.8972) (26.531, 5.4846) (26.7295, 7.2626) (26.785, 8.1913) knots 0 0 0 0 1 1 1 1
  spline S199 degree 3 poles (26.785, 8.1913) (26.8406, 9.12) (26.8009, 9.9058) (26.785, 10.4535) knots 0 0 0 0 1 1 1 1
  spline S200 degree 3 poles (26.785, 10.4535) (26.7692, 11.0011) (26.7612, 11.0408) (26.7057, 11.4853) knots 0 0 0 0 1 1 1 1
  spline S201 degree 3 poles (26.7057, 11.4853) (26.6501, 11.9298) (26.5628, 12.5807) (26.4675, 13.1125) knots 0 0 0 0 1 1 1 1
  spline S202 degree 3 poles (26.4675, 13.1125) (26.3723, 13.6443) (26.2294, 14.2238) (26.1104, 14.6603) knots 0 0 0 0 1 1 1 1
  spline S203 degree 3 poles (26.1104, 14.6603) (25.9913, 15.0969) (25.8881, 15.3747) (25.7532, 15.7319) knots 0 0 0 0 1 1 1 1
  spline S204 degree 3 poles (25.7532, 15.7319) (25.6182, 16.0891) (25.515, 16.3907) (25.3166, 16.8035) knots 0 0 0 0 1 1 1 1
  spline S205 degree 3 poles (25.3166, 16.8035) (25.1182, 17.2162) (24.8404, 17.7718) (24.5625, 18.2322) knots 0 0 0 0 1 1 1 1
  spline S206 degree 3 poles (24.5625, 18.2322) (24.2847, 18.6926) (23.9117, 19.1926) (23.6497, 19.5419) knots 0 0 0 0 1 1 1 1
  spline S207 degree 3 poles (23.6497, 19.5419) (23.3878, 19.8911) (23.2529, 20.042) (22.975, 20.3356) knots 0 0 0 0 1 1 1 1
  spline S208 degree 3 poles (22.975, 20.3356) (22.6972, 20.6293) (22.3004, 21.0103) (21.9829, 21.2881) knots 0 0 0 0 1 1 1 1
  spline S209 degree 3 poles (21.9829, 21.2881) (21.6654, 21.566) (21.4034, 21.7723) (21.07, 22.0025) knots 0 0 0 0 1 1 1 1
  spline S210 degree 3 poles (21.07, 22.0025) (20.7367, 22.2327) (20.3715, 22.4708) (19.9985, 22.6772) knots 0 0 0 0 1 1 1 1
  spline S211 degree 3 poles (19.9985, 22.6772) (19.6254, 22.8836) (19.2603, 23.0661) (18.8079, 23.2328) knots 0 0 0 0 1 1 1 1
  spline S212 degree 3 poles (18.8079, 23.2328) (18.3554, 23.3995) (17.6728, 23.5741) (17.26, 23.6694) knots 0 0 0 0 1 1 1 1
  spline S213 degree 3 poles (17.26, 23.6694) (16.8473, 23.7646) (16.7282, 23.7646) (16.3472, 23.7885) knots 0 0 0 0 1 1 1 1
  spline S214 degree 3 poles (16.3472, 23.7885) (15.9662, 23.8123) (15.3392, 23.8361) (14.9582, 23.8281) knots 0 0 0 0 1 1 1 1
  spline S215 degree 3 poles (14.9582, 23.8281) (14.5772, 23.8202) (14.3549, 23.7885) (14.0454, 23.7488) knots 0 0 0 0 1 1 1 1
  spline S216 degree 3 poles (14.0454, 23.7488) (13.7358, 23.7091) (13.4818, 23.6853) (13.0929, 23.59) knots 0 0 0 0 1 1 1 1
  spline S217 degree 3 poles (13.0929, 23.59) (12.7039, 23.4948) (12.18, 23.3757) (11.7038, 23.1931) knots 0 0 0 0 1 1 1 1
  spline S218 degree 3 poles (11.7038, 23.1931) (11.2275, 23.0106) (10.656, 22.7407) (10.2354, 22.5185) knots 0 0 0 0 1 1 1 1
  spline S219 degree 3 poles (10.2354, 22.5185) (9.8147, 22.2962) (9.4972, 22.0819) (9.1638, 21.8438) knots 0 0 0 0 1 1 1 1
  spline S220 degree 3 poles (9.1638, 21.8438) (8.8304, 21.6056) (8.5447, 21.3596) (8.251, 21.0897) knots 0 0 0 0 1 1 1 1
  spline S221 degree 3 poles (8.251, 21.0897) (7.9573, 20.8198) (7.6715, 20.5103) (7.4175, 20.2166) knots 0 0 0 0 1 1 1 1
  spline S222 degree 3 poles (7.4175, 20.2166) (7.1635, 19.9229) (6.973, 19.6768) (6.7429, 19.3435) knots 0 0 0 0 1 1 1 1
  spline S223 degree 3 poles (6.7429, 19.3435) (6.5127, 19.0101) (6.219, 18.5259) (6.0285, 18.1925) knots 0 0 0 0 1 1 1 1
  spline S224 degree 3 poles (6.0285, 18.1925) (5.838, 17.8591) (5.7665, 17.7401) (5.5919, 17.3591) knots 0 0 0 0 1 1 1 1
  spline S225 degree 3 poles (5.5919, 17.3591) (5.4173, 16.9781) (5.1792, 16.3907) (4.9966, 15.8906) knots 0 0 0 0 1 1 1 1
  spline S226 degree 3 poles (4.9966, 15.8906) (4.814, 15.3906) (4.6553, 14.827) (4.5204, 14.3428) knots 0 0 0 0 1 1 1 1
  spline S227 degree 3 poles (4.5204, 14.3428) (4.3854, 13.8586) (4.314, 13.557) (4.2029, 12.9935) knots 0 0 0 0 1 1 1 1
  spline S228 degree 3 poles (4.2029, 12.9935) (4.0917, 12.4299) (3.9409, 11.5806) (3.8457, 10.9694) knots 0 0 0 0 1 1 1 1
  spline S229 degree 3 poles (3.8457, 10.9694) (3.7504, 10.3582) (3.7028, 9.882) (3.6472, 9.3025) knots 0 0 0 0 1 1 1 1
  spline S230 degree 3 poles (3.6472, 9.3025) (3.5917, 8.7231) (3.552, 8.1357) (3.5282, 7.5166) knots 0 0 0 0 1 1 1 1
  spline S231 degree 3 poles (3.5282, 7.5166) (3.5044, 6.8975) (3.4726, 6.3815) (3.4885, 5.5719) knots 0 0 0 0 1 1 1 1
  spline S232 degree 3 poles (3.4885, 5.5719) (3.5044, 4.7623) (3.544, 3.5875) (3.6075, 2.6747) knots 0 0 0 0 1 1 1 1
  spline S233 degree 3 poles (3.6075, 2.6747) (3.671, 1.7619) (3.7822, 0.857) (3.8854, 0.095) knots 0 0 0 0 1 1 1 1
  spline S234 degree 3 poles (3.8854, 0.095) (3.9885, -0.667) (4.052, -1.1194) (4.2029, -1.8894) knots 0 0 0 0 1 1 1 1
  spline S235 degree 3 poles (4.2029, -1.8894) (4.3537, -2.6593) (4.6077, -3.7944) (4.7982, -4.5484) knots 0 0 0 0 1 1 1 1
  spline S236 degree 3 poles (4.7982, -4.5484) (4.9887, -5.3025) (5.1474, -5.7946) (5.3538, -6.4137) knots 0 0 0 0 1 1 1 1
  spline S237 degree 3 poles (5.3538, -6.4137) (5.5602, -7.0329) (5.8221, -7.7552) (6.0285, -8.279) knots 0 0 0 0 1 1 1 1
  spline S238 degree 3 poles (6.0285, -8.279) (6.2349, -8.8029) (6.3301, -9.049) (6.5841, -9.549) knots 0 0 0 0 1 1 1 1
  spline S239 degree 3 poles (6.5841, -9.549) (6.8381, -10.0491) (7.2509, -10.827) (7.5366, -11.2953) knots 0 0 0 0 1 1 1 1
  spline S240 degree 3 poles (7.5366, -11.2953) (7.8224, -11.7636) (7.989, -12.0017) (8.2907, -12.3669) knots 0 0 0 0 1 1 1 1
  spline S241 degree 3 poles (8.2907, -12.3669) (8.5923, -12.732) (9.0447, -13.1924) (9.3622, -13.4781) knots 0 0 0 0 1 1 1 1
  spline S242 degree 3 poles (9.3622, -13.4781) (9.6797, -13.7639) (9.8782, -13.8909) (10.1957, -14.0734) knots 0 0 0 0 1 1 1 1
  spline S243 degree 3 poles (10.1957, -14.0734) (10.5132, -14.256) (10.9259, -14.4624) (11.2672, -14.5894) knots 0 0 0 0 1 1 1 1
  spline S244 degree 3 poles (11.2672, -14.5894) (11.6085, -14.7164) (11.926, -14.7719) (12.2197, -14.8275) knots 0 0 0 0 1 1 1 1
  spline S245 degree 3 poles (12.2197, -14.8275) (12.5134, -14.883) (12.6722, -14.9069) (13.0135, -14.9069) knots 0 0 0 0 1 1 1 1
  spline S246 degree 3 poles (13.0135, -14.2322) (12.6484, -14.2242) (12.4023, -14.2004) (12.061, -14.1131) knots 0 0 0 0 1 1 1 1
  spline S247 degree 3 poles (12.061, -14.1131) (11.7197, -14.0258) (11.299, -13.8909) (10.9497, -13.7162) knots 0 0 0 0 1 1 1 1
  spline S248 degree 3 poles (10.9497, -13.7162) (10.6005, -13.5416) (10.2592, -13.3114) (9.9575, -13.0812) knots 0 0 0 0 1 1 1 1
  spline S249 degree 3 poles (9.9575, -13.0812) (9.6559, -12.851) (9.4019, -12.5812) (9.1638, -12.3272) knots 0 0 0 0 1 1 1 1
  spline S250 degree 3 poles (9.1638, -12.3272) (8.9257, -12.0732) (8.7907, -11.9224) (8.5288, -11.5334) knots 0 0 0 0 1 1 1 1
  spline S251 degree 3 poles (8.5288, -11.5334) (8.2669, -11.1445) (7.8303, -10.446) (7.5763, -9.9856) knots 0 0 0 0 1 1 1 1
  spline S252 degree 3 poles (7.5763, -9.9856) (7.3223, -9.5252) (7.2032, -9.2792) (6.981, -8.7553) knots 0 0 0 0 1 1 1 1
  spline S253 degree 3 poles (6.981, -8.7553) (6.7587, -8.2314) (6.4809, -7.5805) (6.2269, -6.8503) knots 0 0 0 0 1 1 1 1
  spline S254 degree 3 poles (6.2269, -6.8503) (5.9729, -6.12) (5.711, -5.3184) (5.4729, -4.3897) knots 0 0 0 0 1 1 1 1
  spline S255 degree 3 poles (5.4729, -4.3897) (5.2347, -3.461) (4.9649, -2.1672) (4.7982, -1.294) knots 0 0 0 0 1 1 1 1
  spline S256 degree 3 poles (4.7982, -1.294) (4.6315, -0.4209) (4.568, 0.1585) (4.4807, 0.8491) knots 0 0 0 0 1 1 1 1
  spline S257 degree 3 poles (4.4807, 0.8491) (4.3934, 1.5396) (4.3378, 2.0238) (4.2822, 2.8335) knots 0 0 0 0 1 1 1 1
  spline S258 degree 3 poles (4.2822, 2.8335) (4.2267, 3.6431) (4.1552, 4.675) (4.1632, 5.7306) knots 0 0 0 0 1 1 1 1
  spline S259 degree 3 poles (4.1632, 5.7306) (4.1711, 6.7863) (4.2584, 8.2945) (4.3219, 9.1438) knots 0 0 0 0 1 1 1 1
  spline S260 degree 3 poles (4.3219, 9.1438) (4.3854, 9.9931) (4.4251, 10.1995) (4.5204, 10.8106) knots 0 0 0 0 1 1 1 1
  spline S261 degree 3 poles (4.5204, 10.8106) (4.6156, 11.4218) (4.7664, 12.2711) (4.8775, 12.8347) knots 0 0 0 0 1 1 1 1
  spline S262 degree 3 poles (4.8775, 12.8347) (4.9887, 13.3983) (5.068, 13.7237) (5.195, 14.1841) knots 0 0 0 0 1 1 1 1
  spline S263 degree 3 poles (5.195, 14.1841) (5.322, 14.6445) (5.457, 15.1286) (5.6316, 15.6128) knots 0 0 0 0 1 1 1 1
  spline S264 degree 3 poles (5.6316, 15.6128) (5.8062, 16.097) (6.0602, 16.7082) (6.2269, 17.0813) knots 0 0 0 0 1 1 1 1